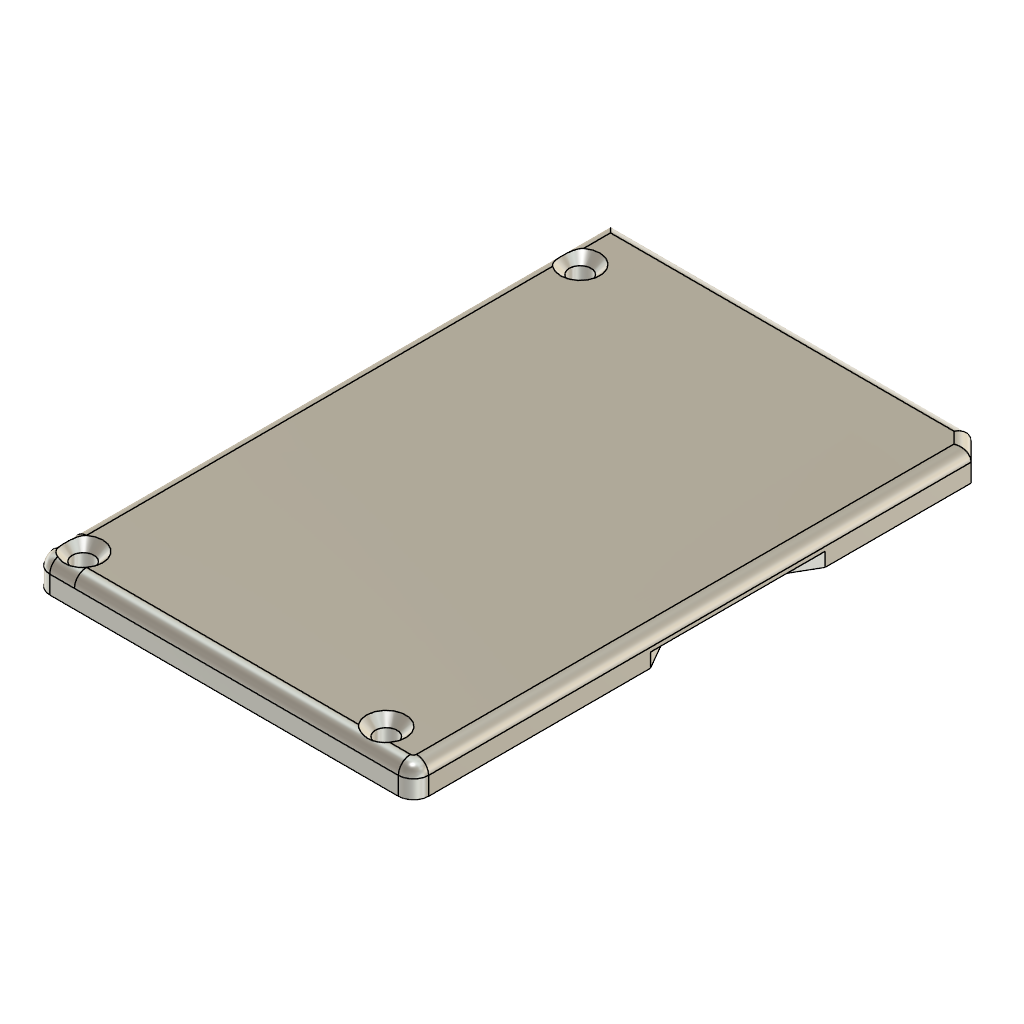
cover (Autodesk Fusion 360 design; units mm, degrees)
part number: 2026-11-14-21-03-26-357
Autodesk Fusion 360 part; units mm, degrees
sketch "Sketch1" plane through (0, 0, 0) normal (0, 0, 1) x (1, 0, 0)
  line L0 (31.25, -47.5) -> (-31.25, -47.5)
  line L1 (-31.25, -47.5) -> (-31.25, 47.5)
  line L2 (-31.25, 47.5) -> (31.25, 47.5)
  line L3 (31.25, 47.5) -> (31.25, -47.5)
  line L4 (31.25, -47.5) -> (-31.25, 47.5) construction
  line L5 (-31.25, -47.5) -> (31.25, 47.5) construction
  dimension "d1" = 62.5
  dimension "d2" = 95
  constraint horizontal L0
  constraint perpendicular L0 L1
  constraint parallel L0 L2
  constraint parallel L1 L3
  constraint coincident L4 origin
  constraint coincident L5 origin
  measures "d1" distance of L0.start L0.end
  measures "d2" distance of L0.start L2.end
extrude "Extrude1" add sketch "Sketch1" along normal blind 5
sketch "Sketch2" plane through (0, 0, 5) normal (0, 0, 1) x (-1, 0, 0)
  line L0 (-31.25, -47.5) -> (31.25, -47.5)
  line L1 (31.25, -47.5) -> (31.25, 47.5)
  line L2 (31.25, 47.5) -> (-31.25, 47.5)
  line L3 (-31.25, 47.5) -> (-31.25, -47.5)
  point P0 (-22.75, 43.5)
  point P1 (27.25, 43.5)
  point P2 (27.25, -38.5)
  dimension "d5" = 8.5
  dimension "d6" = 4
  dimension "d7" = 4
  dimension "d8" = 9
  constraint vertical P1 P2
  constraint horizontal P0 P1
  measures "d5" distance of L3 P0
  measures "d6" distance of L2 P0
  measures "d7" distance of L1 P1
  measures "d8" distance of L0 P2
hole "Hole1" at (-27.25, -43.5, 5) at (22.75, -43.5, 5) at (-27.25, 38.5, 5) direction (0, 0, -1) diameter 3.6 depth 23 tip angle 180 countersink diameter 6.5 countersink angle 90
fillet "Fillet1" radius 2.5 2 edges at (31.25, -47.5, 2.5) (-31.25, -47.5, 2.5)
chamfer "Chamfer1" distance 3 angle 45 1 edges at (31.25, 47.5, 2.5) tangent chain off
sketch "Sketch3" plane through (0, 0, 0) normal (0, 0, -1) x (1, 0, 0)
  line L0 (28.25, -47.5) -> (31.25, -44.5)
  line L1 (31.25, -44.5) -> (31.25, 45)
  arc A0 (31.25, 45) -> (28.75, 47.5) centre (28.75, 45) ccw
  line L2 (28.75, 47.5) -> (-28.75, 47.5)
  arc A1 (-28.75, 47.5) -> (-31.25, 45) centre (-28.75, 45) ccw
  line L3 (-31.25, 45) -> (-31.25, -47.5)
  line L4 (-31.25, -47.5) -> (28.25, -47.5)
  circle A2 centre (-27.25, -38.5) radius 1.8
  circle A3 centre (-27.25, 43.5) radius 1.8
  circle A4 centre (22.75, 43.5) radius 1.8
  line L5 (-27.25, 39.5) -> (-23.25, 39.5)
  line L6 (-23.25, 39.5) -> (-23.25, 43.5)
  line L7 (-23.25, 43.5) -> (19.25, 43.5)
  line L8 (19.25, 43.5) -> (19.25, 39.5)
  line L9 (19.25, 39.5) -> (23.25, 39.5)
  line L10 (23.25, 39.5) -> (23.25, -32.5)
  line L11 (23.25, -32.5) -> (19.25, -32.5)
  line L12 (19.25, -32.5) -> (19.25, -40)
  line L13 (19.25, -40) -> (-19.25, -40)
  line L14 (-19.25, -40) -> (-19.25, -32.5)
  line L15 (-19.25, -32.5) -> (-27.25, -32.5)
  line L16 (-27.25, -32.5) -> (-27.25, 39.5)
  dimension "d17" = 8
  dimension "d18" = 8
  dimension "d19" = 4
  dimension "d20" = 4
  dimension "d23" = 8
  dimension "d24" = 12
  dimension "d25" = 8
  dimension "d26" = 7.5
  dimension "d27" = 15
  dimension "d28" = 15
  dimension "d29" = 12
  dimension "d30" = 12
  constraint horizontal L5
  constraint perpendicular L5 L6
  constraint perpendicular L6 L7
  constraint perpendicular L7 L8
  constraint perpendicular L8 L9
  constraint perpendicular L9 L10
  constraint perpendicular L10 L11
  constraint perpendicular L9 L12
  constraint perpendicular L12 L13
  constraint perpendicular L13 L14
  constraint perpendicular L12 L15
  constraint vertical L16
  measures "d17" distance of L2 L5
  measures "d18" distance of L3 L6
  measures "d19" distance of L2 L7
  measures "d20" distance of L3 L16
  measures "d23" distance of L1 L10
  measures "d24" distance of L1 L8
  measures "d25" distance of L2 L9
  measures "d26" distance of L4 L13
  measures "d27" distance of L4 L11
  measures "d28" distance of L4 L15
  measures "d29" distance of L1 L12
  measures "d30" distance of L3 L14
extrude "Extrude2" cut sketch "Sketch3" against normal blind 3 contours L5 L6 L7 L8 L9 L10 L11 L12 L13 L14 L15 L16
fillet "Fillet2" radius 3 12 edges at (19.25, -39.5, 1.5) (23.25, -39.5, 1.5) (19.25, -43.5, 1.5) (-23.25, -43.5, 1.5) (-23.25, -39.5, 1.5) (-27.25, -39.5, 1.5) (-27.25, 32.5, 1.5) (-19.25, 32.5, 1.5) (-19.25, 40, 1.5) (19.25, 40, 1.5) (19.25, 32.5, 1.5) (23.25, 32.5, 1.5)
fillet "Fillet3" radius 2 7 edges at (-31.25, 1.25, 5) (-30.5178, -46.7678, 5) (0, -47.5, 5) (30.5178, -46.7678, 5) (31.25, -0.25, 5) (29.75, 46, 5) (-1.5, 47.5, 5)
ref_plane "WorkPlane1" through (0, 6, 2.5) normal (0, 1, 0) x (-1, 0, 0)
sketch "Sketch4" plane through (0, 6, 0) normal (0, 1, 0) x (1, 0, 0)
  line L0 (19.25, 0) -> (21.25, 0)
  line L1 (19.25, 0) -> (16.25, 0)
  line L2 (16.25, 0) -> (-16.25, 0)
  line L3 (-16.25, 0) -> (-19.25, 0)
  line L4 (-22.25, 0) -> (-19.25, 0)
  line L5 (-22.25, 0) -> (-24.25, 0)
  line L6 (-24.25, 0) -> (-27.25, 0)
  line L7 (-25.1208, 0) -> (-27.25, 0)
  line L8 (-25.1208, 0) -> (-23.1208, 0)
  line L9 (-20.25, 0) -> (-23.1208, 0)
  line L10 (-20.25, 0) -> (16.25, 0)
  line L11 (19.1208, 0) -> (16.25, 0)
  line L12 (19.1208, 0) -> (21.1208, 0)
  line L13 (23.25, 0) -> (21.1208, 0)
  line L14 (23.25, 0) -> (21.25, 0)
  line L15 (28.25, 0) -> (31.25, 0)
  line L16 (28.75, 0) -> (31.25, 0)
  line L17 (28.75, 0) -> (-28.75, 0)
  line L18 (-31.25, 0) -> (-28.75, 0)
  line L19 (-31.25, 0) -> (28.25, 0)
  line L20 (-29.05, 0) -> (-25.45, 0)
  line L21 (-29.05, 0) -> (-25.45, 0)
  line L22 (20.95, 0) -> (24.55, 0)
  line L23 (31.25, -3) -> (31.25, 0)
  line L24 (31.25, 0) -> (31.25, -3)
  line L25 (27.25, 0) -> (31.25, -2.3094)
  dimension "d39" = 4
  dimension "d40" = 30
  constraint coincident L17 L25.start
  constraint coincident L23 L25.end
  measures "d39" distance of L15.end L25.start
  measures "d40" angle of L15 L25
extrude "Extrude3" cut sketch "Sketch4" along normal mid plane 15
chamfer "Chamfer2" distance 6.9 angle 30 2 edges at (31.25, 13.5, 1.1547) (31.25, -1.5, 1.1547) measured on face at (31.25, -30.5, 1.7698) measured on face at (31.25, -30.5, 1.7698) tangent chain off
